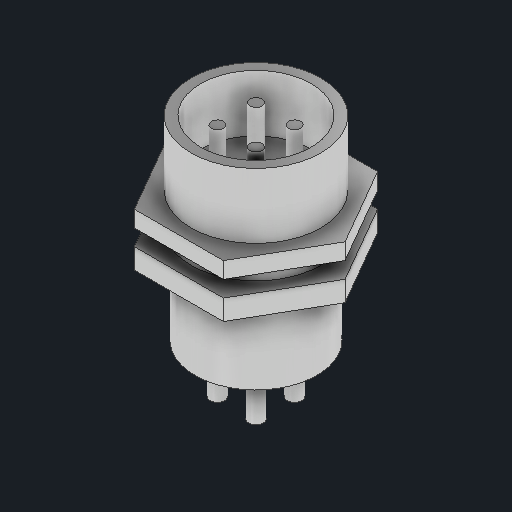
# Autodesk Inventor part: gx16_4pin_panel_socket
Saved by Autodesk Inventor 2027.1 (Build 311270010, 270A)
## iProperties
Created: 2026-11-03
Part Number: gx16_4pin_panel_socket
Material: Generic
Document SubType Name: Modeling
Designer: alexg
Density: 1 g/cm^3
Appearance: Chrome - Polished
Author: alexg
Autodesk Inventor part; units mm, degrees
ref_plane "Work Plane1" through (0, -2, 0) normal (0, 1, 0) x (-1, 0, 0)
sketch "Thread (through panel) sketch" plane through (0, -2, 0) normal (0, 1, 0) x (-1, 0, 0)
  circle A0 centre (0, 0) radius 8
  constraints: 1 centre point
extrude "Thread (through panel)" add sketch "Thread (through panel) sketch" along normal blind 12
ref_plane "Work Plane2" through (0, 10, 0) normal (0, 1, 0) x (-1, 0, 0)
sketch "Pin cavity sketch" plane through (0, 10, 0) normal (0, 1, 0) x (-1, 0, 0)
  circle A0 centre (0, 0) radius 6.8
  constraints: 1 centre point
extrude "Pin cavity" cut sketch "Pin cavity sketch" against normal blind 7
ref_plane "Work Plane3" through (0, 3, 0) normal (0, 1, 0) x (-1, 0, 0)
sketch "Pins x4 sketch" plane through (0, 3, 0) normal (0, 1, 0) x (-1, 0, 0)
  circle A0 centre (-2.3759, 2.3759) radius 0.75
  circle A1 centre (2.3759, 2.3759) radius 0.75
  circle A2 centre (2.3759, -2.3759) radius 0.75
  circle A3 centre (-2.3759, -2.3759) radius 0.75
  constraints: 4 centre point
extrude "Pins x4" add sketch "Pins x4 sketch" along normal blind 6
sketch "Outer nut sketch" plane through (0, 0, 0) normal (0, 1, 0) x (-1, 0, 0)
  line L0 (-10.9697, 0) -> (-5.4848, 9.5)
  line L1 (-5.4848, 9.5) -> (5.4848, 9.5)
  line L2 (5.4848, 9.5) -> (10.9697, 0)
  line L3 (10.9697, 0) -> (5.4848, -9.5)
  line L4 (5.4848, -9.5) -> (-5.4848, -9.5)
  line L5 (-5.4848, -9.5) -> (-10.9697, 0)
  circle A0 centre (0, 0) radius 8
  constraints: 12 end point, 1 centre point
extrude "Outer nut" add sketch "Outer nut sketch" along normal blind 2
ref_plane "Work Plane4" through (0, -2, 0) normal (0, 1, 0) x (-1, 0, 0)
sketch "Inner flange sketch" plane through (0, -2, 0) normal (0, 1, 0) x (-1, 0, 0)
  line L0 (-10.9697, 0) -> (-5.4848, 9.5)
  line L1 (-5.4848, 9.5) -> (5.4848, 9.5)
  line L2 (5.4848, 9.5) -> (10.9697, 0)
  line L3 (10.9697, 0) -> (5.4848, -9.5)
  line L4 (5.4848, -9.5) -> (-5.4848, -9.5)
  line L5 (-5.4848, -9.5) -> (-10.9697, 0)
  constraints: 12 end point
extrude "Inner flange" add sketch "Inner flange sketch" against normal blind 2.5
ref_plane "Work Plane5" through (0, -4.5, 0) normal (0, 1, 0) x (-1, 0, 0)
sketch "Rear body sketch" plane through (0, -4.5, 0) normal (0, 1, 0) x (-1, 0, 0)
  circle A0 centre (0, 0) radius 7.5
  constraints: 1 centre point
extrude "Rear body" add sketch "Rear body sketch" against normal blind 9.5
ref_plane "Work Plane6" through (0, -14, 0) normal (0, 1, 0) x (-1, 0, 0)
sketch "Solder cups x4 sketch" plane through (0, -14, 0) normal (0, 1, 0) x (-1, 0, 0)
  circle A0 centre (-2.3759, 2.3759) radius 0.9
  circle A1 centre (2.3759, 2.3759) radius 0.9
  circle A2 centre (2.3759, -2.3759) radius 0.9
  circle A3 centre (-2.3759, -2.3759) radius 0.9
  constraints: 4 centre point
extrude "Solder cups x4" add sketch "Solder cups x4 sketch" against normal blind 6
body "Solid1"
